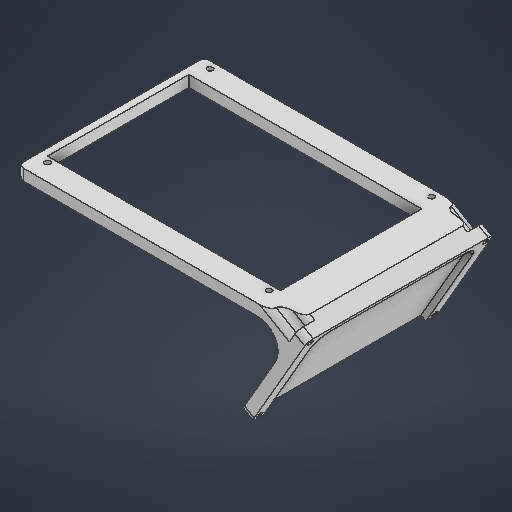
# Autodesk Inventor part: STAND PARTS
Saved by Autodesk Inventor 2027.1 (Build 311270010, 270A)
## iProperties
Created: 2026-10-10
Part Number: STAND PARTS
Material: 일반
Document SubType Name: Modeling
Designer: work
Density: 1 g/cm^3
Appearance: 기본값
Author: work
Autodesk Inventor part; units mm, degrees
ref_plane "YZ Plane" through (0, 0, 0) normal (1, 0, 0) x (0, 1, 0)
ref_plane "XZ Plane" through (0, 0, 0) normal (0, 1, 0) x (-1, 0, 0)
ref_plane "XY Plane" through (0, 0, 0) normal (0, 0, 1) x (1, 0, 0)
sketch "스케치1" plane through (0, 0, 0) normal (0, 1, 0) x (-1, 0, 0)
  line L0 (0, 0) -> (165.5, 0)
  line L1 (165.5, 0) -> (165.5, -100.5)
  line L2 (165.5, -100.5) -> (0, -100.5)
  line L3 (0, -100.5) -> (0, 0)
  line L4 (4, 0) -> (4, 4) construction
  circle A0 centre (4, 4) radius 2
  line L5 (82.75, 0) -> (82.75, -100.5) construction
  line L6 (4, -100.5) -> (4, -111.5) construction
  circle A1 centre (4, -111.5) radius 2
  line L7 (161.5, 0) -> (161.5, 4) construction
  circle A2 centre (161.5, 4) radius 2
  line L8 (161.5, -100.5) -> (161.5, -111.5) construction
  circle A3 centre (161.5, -111.5) radius 2
  line L9 (170.5, 16) -> (-5, 16)
  line L10 (-5, 16) -> (-5, -116.5)
  line L11 (-5, -116.5) -> (170.5, -116.5)
  line L12 (170.5, -116.5) -> (170.5, 16)
  line L13 (-5, 16) -> (-25, 16)
  line L14 (-25, 16) -> (-25, -116.5)
  line L15 (-25, -116.5) -> (-5, -116.5)
  line L16 (-5, -116.5) -> (-5, 16)
  dimension "d0" = 165.5
  dimension "d1" = 100.5
  dimension "d2" = 4
  dimension "d3" = 4
  dimension "d4" = 4
  dimension "d5" = 4
  dimension "d6" = 4
  dimension "d7" = 11
  dimension "d8" = 5
  dimension "d9" = 5
  dimension "d11" = 5
  dimension "d12" = 16
  dimension "d15" = 20
  constraints: 34 end point, 6 parallel, 6 symmetric about line, 4 centre point, 4 coincident, 3 horizontal, 3 perpendicular, 2 midpoint, 2 point on line, 2 vertical, 2 other
  measures "d0" distance of L1.end L2.end
  measures "d1" distance of L0.end L1.end
  measures "d2" distance of L4.start L4.end
  measures "d3" diameter of A0
  measures "d4" distance from line of L3 L4.end
  measures "d5" diameter of A1
  measures "d6" distance between parallel lines of L3 L6
  measures "d7" distance of L6.start L6.end
  measures "d8" distance between parallel lines of L10 L3
  measures "d9" distance between parallel lines of L12 L1
  measures "d11" distance from line of L11 L8.end
  measures "d12" distance between parallel lines of L9 L0
  measures "d15" distance of L14.end L10.end
extrude "돌출1" add sketch "스케치1" along normal blind 8 contours L12 L11 L10 L9
extrude "돌출2" add sketch "스케치1" along normal up to surface (8 mm away) contours L10 L15 L14 L13
sketch "스케치2" plane through (-170.5, 0, -116.5) normal (0, 0, -1) x (-1, 0, 0)
  line L0 (-195.5, 0) -> (-195.5, 8) projected
  line L1 (-195.5, 8) -> (-205.8923, 2)
  line L2 (-205.8923, 2) -> (-165.8923, -67.282)
  line L3 (0, 8) -> (-195.5, 8) projected
  line L4 (-195.5, 0) -> (0, 0) projected
  line L5 (-195.5, 0) -> (-158.9641, -63.282)
  line L6 (-158.9641, -63.282) -> (-165.8923, -67.282)
  line L7 (-170.5, 0) -> (-170.5, 8) projected
  line L8 (-170.5, 0) -> (-170.5, 8) projected
  arc A0 (-170.5, 0) -> (-183, -21.6506) centre (-170.5, -14.4338) ccw
  dimension "d18" = 60
  dimension "d20" = 80
  dimension "d21" = 8
  constraints: 8 end point, 2 perpendicular, 2 point on circle, 2 tangent, 1 centre point, 1 parallel, 1 point on line
  measures "d18" angle of L2 L3
  measures "d20" distance of L1.end L2.end
  measures "d21" distance between parallel lines of L2 L5
extrude "돌출3" add sketch "스케치2" against normal up to surface (132.5 mm away) contours L5 L6 L2 L1 L0 | L4 A0 L5
sketch "스케치3" plane through (-4.6077, -67.282, 16) normal (0.8660254, -0.5, 0) x (0, 0, -1)
  line L0 (0, 80) -> (0, 0) construction
  line L1 (132.5, 0) -> (0, 0) construction
  line L2 (132.5, 80) -> (132.5, 0) construction
  line L3 (132.5, 80) -> (0, 80) construction
  line L4 (4, 4) -> (4, 76) construction
  line L5 (4, 76) -> (128.5, 76) construction
  line L6 (128.5, 76) -> (128.5, 4) construction
  line L7 (128.5, 4) -> (4, 4) construction
  circle A0 centre (4, 76) radius 2
  circle A1 centre (128.5, 76) radius 2
  circle A2 centre (128.5, 4) radius 2
  circle A3 centre (4, 4) radius 2
  line L8 (8.5, -31.5) -> (124, -31.5)
  line L9 (124, -31.5) -> (124, 66)
  line L10 (114, 76) -> (18.5, 76)
  line L11 (8.5, 66) -> (8.5, -31.5)
  arc A4 (18.5, 76) -> (8.5, 66) centre (18.5, 66) ccw
  arc A5 (124, 66) -> (114, 76) centre (114, 66) ccw
  point P0 (16, 60.5718)
  point P1 (124, 76)
  point P2 (8.5, 76)
  point P3 (66.25, 76)
  point P4 (66.25, 76)
  dimension "d24" = 4
  dimension "d25" = 4
  dimension "d26" = 4
  dimension "d27" = 4
  dimension "d28" = 4
  dimension "d29" = 115.5
  dimension "d30" = 107.5
  dimension "d31" = 10
  constraints: 16 end point, 6 centre point, 5 coincident, 4 point on circle, 4 point on line, 4 tangent, 3 midpoint, 2 parallel, 1 equal radius, 1 horizontal, 1 perpendicular, 3 other
  measures "d24" distance between parallel lines of L0 L4
  measures "d25" diameter of A0
  measures "d26" diameter of A1
  measures "d27" diameter of A2
  measures "d28" diameter of A3
  measures "d29" distance of point (124, 76) point (8.5, 76)
  measures "d30" distance of point (8.5, 76) L8.start
  measures "d31" radius of A4
extrude "돌출4" cut sketch "스케치3" against normal blind 4 contours L11 A4 L10 A5 L9 L8
extrude "돌출5" cut sketch "스케치3" against normal blind 8 contours A0 | A1 | A2 | A3
extrude "돌출6" cut sketch "스케치3" against normal through all contours A0 | A1
sketch "스케치4" plane through (12.5, -21.6506, -116.5) normal (-0.8660254, 0.5, 0) x (0, 0, 1)
  circle A0 centre (4, -44.0718) radius 2 projected
  circle A1 centre (128.5, -44.0718) radius 2 projected
  line L0 (132.5, -48.0718) -> (132.5, 0) projected
  line L1 (0, 0) -> (132.5, 0) projected
  line L2 (0, -48.0718) -> (0, 0) projected
  line L3 (0, -48.0718) -> (132.5, -48.0718) projected
  circle A2 centre (4, -44.0718) radius 2 projected
  circle A3 centre (128.5, 27.9282) radius 2 projected
  circle A4 centre (4, 27.9282) radius 2 projected
  circle A5 centre (128.5, -44.0718) radius 2 projected
  line L4 (124, -48.0718) -> (124, 17.9282) projected
  arc A6 (124, 17.9282) -> (114, 27.9282) centre (114, 17.9282) ccw projected
  line L5 (114, 27.9282) -> (18.5, 27.9282) projected
  arc A7 (18.5, 27.9282) -> (8.5, 17.9282) centre (18.5, 17.9282) ccw projected
  line L6 (8.5, 17.9282) -> (8.5, -48.0718) projected
  line L7 (0, -48.0718) -> (8.5, -48.0718) projected
  line L8 (0, 31.9282) -> (0, -48.0718) projected
  line L9 (0, 31.9282) -> (132.5, 31.9282) projected
  line L10 (132.5, 31.9282) -> (132.5, -48.0718) projected
  line L11 (124, -48.0718) -> (132.5, -48.0718) projected
  circle A8 centre (128.5, 27.9282) radius 4
  line L12 (0, 31.9282) -> (132.5, 31.9282) projected
  circle A9 centre (4, 27.9282) radius 4
  line L13 (124.5, 27.9282) -> (124.5, 31.9282)
  line L14 (128.5, 23.9282) -> (132.5, 23.9282)
  line L15 (4, 23.9282) -> (0, 23.9282)
  line L16 (8, 27.9282) -> (8, 31.9282)
  point P0 (116.5, 12.5)
  point P1 (128.5, 31.9282)
  point P2 (132.5, 27.9282)
  point P3 (0, 27.9282)
  point P4 (4, 31.9282)
  point P5 (8, 31.9282)
  constraints: 8 end point, 6 point on line, 5 tangent, 4 point on circle, 3 perpendicular, 2 centre point, 2 coincident
extrude "돌출7" cut sketch "스케치4" along normal through all contours L14 A8 L10 | A8 L9 L10 | A8 | A8 L13 L9 | L8 A9 L15 | L8 L9 A9 | A9 | L16 A9 L9
fillet "모깎기1" radius 4 10 edges at (31.9282, 4, 16) (31.9282, 4, -116.5) (-8.0718, -65.282, 16) (-8.0718, -65.282, -116.5) (-170.5, 4, -116.5) (-170.5, 4, 16) (26.7321, 7, -108.5) (16.7321, 3.5359, -116.5) (16.7321, 3.5359, 16) (26.7321, 7, 8)
